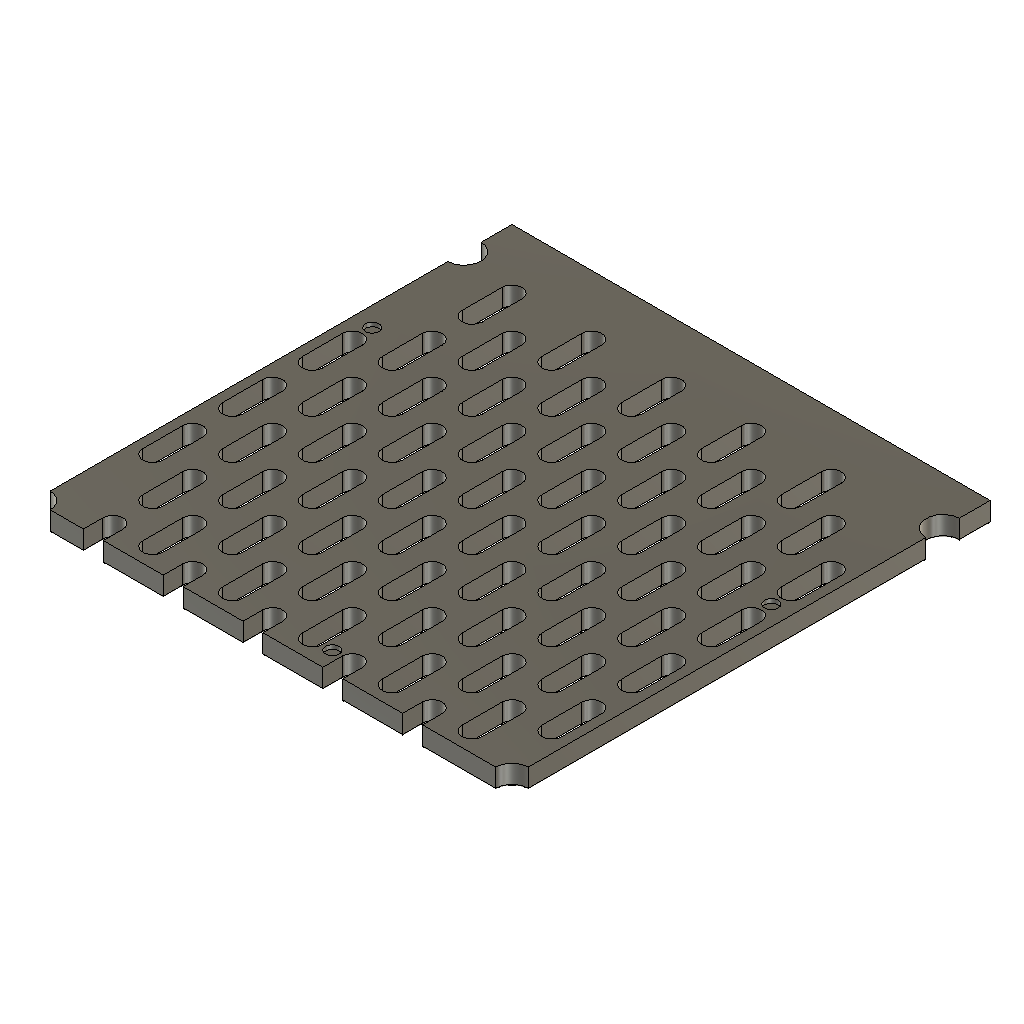
panel-top-edge-v02 (Autodesk Fusion 360 design; units mm, degrees)
part number: 2026-10-27-14-47-49-587
part number: 2026-10-27-14-47-50-048
Autodesk Fusion 360 part; units mm, degrees
sketch "01 Panel blank sketch" plane through (0, 0, 0) normal (0, 0, 1) x (1, 0, 0) in component "Panel top-edge"
  line L0 (0.1, 0.1) -> (119.9, 0.1)
  line L1 (119.9, 0.1) -> (119.9, 119.9)
  line L2 (119.9, 119.9) -> (0.1, 119.9)
  line L3 (0.1, 119.9) -> (0.1, 0.1)
  dimension "d31" = 0.1
  dimension "d32" = 0.1
  dimension "d33" = 119.8
  dimension "d34" = 119.8
  constraint horizontal L0
  constraint vertical L1
  constraint horizontal L2
  constraint vertical L3
  measures "d31" horizontal distance of origin L0.start
  measures "d32" vertical distance of origin L0.start
  measures "d33" horizontal distance of L0.start L0.end
  measures "d34" vertical distance of L0.end L1.end
extrude "01 Panel blank" add sketch "01 Panel blank sketch" along normal blind 5 in component "Panel top-edge"
sketch "03 A main constrained seed" plane through (0, 0, 0) normal (0, 0, 1) x (1, 0, 0) in component "Panel top-edge"
  line L0 (27.5, 5) -> (27.5, 15)
  arc A0 (27.5, 15) -> (22.5, 15) centre (25, 15) ccw
  line L1 (22.5, 15) -> (22.5, 5)
  arc A1 (22.5, 5) -> (27.5, 5) centre (25, 5) ccw
  line L2 (25, 5) -> (25, 15) construction
  line L3 (25, 5) -> (35, 5) construction
  dimension "d37" = 5
  dimension "d38" = 10
  dimension "d39" = 90
  dimension "d40" = 10
  dimension "d41" = 25
  dimension "d42" = 5
  constraint tangent L0 A0
  constraint tangent A0 L1
  constraint tangent L1 A1
  constraint tangent L0 A1
  constraint parallel L0 L1
  constraint horizontal L3
  measures "d37" diameter of A0
  measures "d38" distance of A1.centre A0.centre
  measures "d39" angle of L2 L3
  measures "d40" horizontal distance of A1.centre L3.end
  measures "d41" horizontal distance of origin A1.centre
  measures "d42" vertical distance of origin A1.centre
extrude "03 A main through cut" cut sketch "03 A main constrained seed" along normal blind 5 in component "Panel top-edge"
pattern_linear "03 A main lattice" count 5 spacing 20 along (1, 0, 0) count 5 spacing 20 along (0, 1, 0) of "03 A main through cut" in component "Panel top-edge"
sketch "04 A end strip constrained seed" plane through (0, 0, 0) normal (0, 0, 1) x (1, 0, 0) in component "Panel top-edge"
  line L0 (7.5, 25) -> (7.5, 35)
  arc A0 (7.5, 35) -> (2.5, 35) centre (5, 35) ccw
  line L1 (2.5, 35) -> (2.5, 25)
  arc A1 (2.5, 25) -> (7.5, 25) centre (5, 25) ccw
  line L2 (5, 25) -> (5, 35) construction
  line L3 (5, 25) -> (15, 25) construction
  dimension "d49" = 5
  dimension "d50" = 10
  dimension "d51" = 90
  dimension "d52" = 10
  dimension "d53" = 5
  dimension "d54" = 25
  constraint tangent L0 A0
  constraint tangent A0 L1
  constraint tangent L1 A1
  constraint tangent L0 A1
  constraint parallel L0 L1
  constraint horizontal L3
  measures "d49" diameter of A0
  measures "d50" distance of A1.centre A0.centre
  measures "d51" angle of L2 L3
  measures "d52" horizontal distance of A1.centre L3.end
  measures "d53" horizontal distance of origin A1.centre
  measures "d54" vertical distance of origin A1.centre
extrude "04 A end strip through cut" cut sketch "04 A end strip constrained seed" along normal blind 5 in component "Panel top-edge"
pattern_linear "04 A end strip lattice" count 1 spacing 20 along (1, 0, 0) count 3 spacing 20 along (0, 1, 0) of "04 A end strip through cut" in component "Panel top-edge"
sketch "05 B main constrained seed" plane through (0, 0, 0) normal (0, 0, 1) x (1, 0, 0) in component "Panel top-edge"
  line L0 (17.5, -5) -> (17.5, 5)
  arc A0 (17.5, 5) -> (12.5, 5) centre (15, 5) ccw
  line L1 (12.5, 5) -> (12.5, -5)
  arc A1 (12.5, -5) -> (17.5, -5) centre (15, -5) ccw
  line L2 (15, -5) -> (15, 5) construction
  line L3 (15, -5) -> (25, -5) construction
  dimension "d61" = 5
  dimension "d62" = 10
  dimension "d63" = 90
  dimension "d64" = 10
  dimension "d65" = 15
  dimension "d66" = 5
  constraint tangent L0 A0
  constraint tangent A0 L1
  constraint tangent L1 A1
  constraint tangent L0 A1
  constraint parallel L0 L1
  constraint horizontal L3
  measures "d61" diameter of A0
  measures "d62" distance of A1.centre A0.centre
  measures "d63" angle of L2 L3
  measures "d64" horizontal distance of A1.centre L3.end
  measures "d65" horizontal distance of origin A1.centre
  measures "d66" vertical distance of origin A1.centre
extrude "05 B main through cut" cut sketch "05 B main constrained seed" along normal blind 5 in component "Panel top-edge"
pattern_linear "05 B main lattice" count 5 spacing 20 along (1, 0, 0) count 6 spacing 20 along (0, 1, 0) of "05 B main through cut" in component "Panel top-edge"
sketch "06 B end strip constrained seed" plane through (0, 0, 0) normal (0, 0, 1) x (1, 0, 0) in component "Panel top-edge"
  line L0 (117.5, 15) -> (117.5, 25)
  arc A0 (117.5, 25) -> (112.5, 25) centre (115, 25) ccw
  line L1 (112.5, 25) -> (112.5, 15)
  arc A1 (112.5, 15) -> (117.5, 15) centre (115, 15) ccw
  line L2 (115, 15) -> (115, 25) construction
  line L3 (115, 15) -> (125, 15) construction
  dimension "d73" = 5
  dimension "d74" = 10
  dimension "d75" = 90
  dimension "d76" = 10
  dimension "d77" = 115
  dimension "d78" = 15
  constraint tangent L0 A0
  constraint tangent A0 L1
  constraint tangent L1 A1
  constraint tangent L0 A1
  constraint parallel L0 L1
  constraint horizontal L3
  measures "d73" diameter of A0
  measures "d74" distance of A1.centre A0.centre
  measures "d75" angle of L2 L3
  measures "d76" horizontal distance of A1.centre L3.end
  measures "d77" horizontal distance of origin A1.centre
  measures "d78" vertical distance of origin A1.centre
extrude "06 B end strip through cut" cut sketch "06 B end strip constrained seed" along normal blind 5 in component "Panel top-edge"
pattern_linear "06 B end strip lattice" count 1 spacing 20 along (1, 0, 0) count 4 spacing 20 along (0, 1, 0) of "06 B end strip through cut" in component "Panel top-edge"
sketch "07 Shared node clearance sketch" plane through (0, 0, 0) normal (0, 0, 1) x (1, 0, 0) in component "Panel top-edge"
  circle A0 centre (0, 0) radius 4.2
  dimension "d85" = 8.4
  constraint coincident A0.centre origin
  measures "d85" diameter of A0
extrude "07 Shared node clearance" cut sketch "07 Shared node clearance sketch" along normal blind 5 in component "Panel top-edge"
sketch "07 Shared node clearance sketch (1)" plane through (0, 0, 0) normal (0, 0, 1) x (1, 0, 0) in component "Panel top-edge"
  circle A0 centre (0, 108) radius 4.2
  dimension "d88" = 108
  dimension "d89" = 8.4
  constraint vertical origin A0.centre
  measures "d88" vertical distance of origin A0.centre
  measures "d89" diameter of A0
extrude "07 Shared node clearance (1)" cut sketch "07 Shared node clearance sketch (1)" along normal blind 5 in component "Panel top-edge"
sketch "07 Shared node clearance sketch (2)" plane through (0, 0, 0) normal (0, 0, 1) x (1, 0, 0) in component "Panel top-edge"
  circle A0 centre (120, 0) radius 4.2
  dimension "d92" = 120
  dimension "d93" = 8.4
  constraint horizontal origin A0.centre
  measures "d92" horizontal distance of origin A0.centre
  measures "d93" diameter of A0
extrude "07 Shared node clearance (2)" cut sketch "07 Shared node clearance sketch (2)" along normal blind 5 in component "Panel top-edge"
sketch "07 Shared node clearance sketch (3)" plane through (0, 0, 0) normal (0, 0, 1) x (1, 0, 0) in component "Panel top-edge"
  circle A0 centre (120, 108) radius 4.2
  dimension "d96" = 120
  dimension "d97" = 108
  dimension "d98" = 8.4
  measures "d96" horizontal distance of origin A0.centre
  measures "d97" vertical distance of origin A0.centre
  measures "d98" diameter of A0
extrude "07 Shared node clearance (3)" cut sketch "07 Shared node clearance sketch (3)" along normal blind 5 in component "Panel top-edge"
fillet "08 Rounded slot entrances and face edges" radius 0.4 2 faces at (51.7289, 115.7643, 0) (51.7289, 115.7643, 0) in component "Panel top-edge"
ref_plane "WorkPlane1" through (0, 0, 5) normal (0, 0, 1) x (1, 0, 0) in component "Panel top-edge"
sketch "09 Blind rear key socket sketch" plane through (0, 0, 5) normal (0, 0, 1) x (1, 0, 0) in component "Panel top-edge"
  circle A0 centre (5, 80) radius 1.7
  dimension "d105" = 5
  dimension "d106" = 80
  dimension "d107" = 3.4
  measures "d105" horizontal distance of origin A0.centre
  measures "d106" vertical distance of origin A0.centre
  measures "d107" diameter of A0
extrude "09 Blind rear key socket" cut sketch "09 Blind rear key socket sketch" against normal blind 1 in component "Panel top-edge"
ref_plane "WorkPlane2" through (0, 0, 5) normal (0, 0, 1) x (1, 0, 0) in component "Panel top-edge"
sketch "09 Blind rear key socket sketch (1)" plane through (0, 0, 5) normal (0, 0, 1) x (1, 0, 0) in component "Panel top-edge"
  circle A0 centre (115, 70) radius 1.7
  dimension "d112" = 115
  dimension "d113" = 70
  dimension "d114" = 3.4
  measures "d112" horizontal distance of origin A0.centre
  measures "d113" vertical distance of origin A0.centre
  measures "d114" diameter of A0
extrude "09 Blind rear key socket (1)" cut sketch "09 Blind rear key socket sketch (1)" against normal blind 1 in component "Panel top-edge"
ref_plane "WorkPlane3" through (0, 0, 5) normal (0, 0, 1) x (1, 0, 0) in component "Panel top-edge"
sketch "09 Blind rear key socket sketch (2)" plane through (0, 0, 5) normal (0, 0, 1) x (1, 0, 0) in component "Panel top-edge"
  circle A0 centre (70, 5) radius 1.7
  dimension "d119" = 70
  dimension "d120" = 5
  dimension "d121" = 3.4
  measures "d119" horizontal distance of origin A0.centre
  measures "d120" vertical distance of origin A0.centre
  measures "d121" diameter of A0
extrude "09 Blind rear key socket (2)" cut sketch "09 Blind rear key socket sketch (2)" against normal blind 1 in component "Panel top-edge"
component "Panel top-edge" placed x (1, 0, 0) y (0, 1, 0) z (0, 0, 1) at (0, 0, 0)
equation "columns = 6" comment "Even integer 4..14; each cell is 20 mm"
equation "rows = 6" comment "Even integer 4..14"
equation "pitch = 20 mm" comment "Keep for dense SKADIS compatible lattice"
equation "panelWidth = columns * pitch" comment "Nominal module pitch X"
equation "panelHeight = rows * pitch" comment "Nominal module pitch Y"
equation "seamGap = 0.2 mm" comment "Physical envelope shrinks around fixed lattice"
equation "boardThickness = 5 mm" comment "Fit-test with real hooks"
equation "slotWidth = 5 mm" comment "Minimum throat width"
equation "slotHeight = 15 mm" comment "Minimum throat height"
equation "entryRadius = 0.4 mm" comment "Front slot and perimeter edge rounding"
equation "cornerRadius = 6 mm" comment "Plan-view panel corner rounding"
equation "hookClearance = 10 mm" comment "PROVISIONAL: board rear to front of extrusion"
equation "frameZ = boardThickness + hookClearance" comment "Front extrusion datum"
equation "mountInset = 12 mm" comment "Exterior node inset from outside module edge"
equation "mountBore = 8.4 mm" comment "Clearance around 8 mm metal shoulder"
equation "capDiameter = 18 mm" comment "Visible decorative mounting disk"
equation "capThickness = 2 mm" comment "Metal clamping cap / washer"
equation "seatThickness = 2 mm" comment "Printed rear bearing washer"
equation "screwDiameter = 5 mm" comment "Nominal M5 reference, threads omitted"
equation "screwClearance = 5.5 mm" comment "Cap and spacer bore"
equation "keyWidth = 4 mm" comment "Registration key corridor width"
equation "keyThickness = 2 mm" comment "Rear removable key body"
equation "keyPegDiameter = 3 mm" comment "Rear locating peg"
equation "keySocketDiameter = 3.4 mm" comment "0.2 mm radial starting fit"
equation "keyPegHeight = 0.8 mm" comment "Peg penetration"
equation "keySocketDepth = 1 mm" comment "Blind locating pocket"
equation "panelLeft = 0" comment "0 internal / 1 finished; full cell border and inset mounting"
equation "panelRight = 0" comment "0 internal / 1 finished; full cell border and inset mounting"
equation "panelBottom = 0" comment "0 internal / 1 finished; full cell border and inset mounting"
equation "panelTop = 1" comment "0 internal / 1 finished; full cell border and inset mounting"
equation "d31 = abs(( 0 mm ) + seamGap / 2)"
equation "d32 = abs(( 0 mm ) + seamGap / 2)"
equation "d33 = panelWidth - seamGap"
equation "d34 = panelHeight - seamGap"
equation "d35 = boardThickness"
equation "d37 = slotWidth"
equation "d38 = slotHeight - slotWidth"
equation "d40 = pitch / 2"
equation "d41 = abs(( 0 mm ) + pitch / 4 + pitch * ( panelLeft + 1 ))"
equation "d42 = abs(( ( 0 mm ) + pitch / 2 + pitch * panelBottom ) - ( slotHeight - slotWidth ) / 2)"
equation "d43 = boardThickness"
equation "d45 = columns - panelLeft - panelRight - 1"
equation "d46 = rows - panelBottom - panelTop"
equation "d47 = pitch"
equation "d48 = pitch"
equation "d49 = slotWidth"
equation "d50 = slotHeight - slotWidth"
equation "d52 = pitch / 2"
equation "d53 = abs(( 0 mm ) + pitch / 4 + pitch * panelLeft)"
equation "d54 = abs(( ( 0 mm ) + 3 * pitch / 2 + pitch * panelBottom ) - ( slotHeight - slotWidth ) / 2)"
equation "d55 = boardThickness"
equation "d58 = rows - panelBottom - panelTop - 2"
equation "d59 = pitch"
equation "d60 = pitch"
equation "d61 = slotWidth"
equation "d62 = slotHeight - slotWidth"
equation "d64 = pitch / 2"
equation "d65 = abs(( 0 mm ) + 3 * pitch / 4 + pitch * panelLeft)"
equation "d66 = abs(( ( 0 mm ) + pitch * panelBottom ) - ( slotHeight - slotWidth ) / 2)"
equation "d67 = boardThickness"
equation "d69 = columns - panelLeft - panelRight - 1"
equation "d70 = rows + 1 - panelBottom - panelTop"
equation "d71 = pitch"
equation "d72 = pitch"
equation "d73 = slotWidth"
equation "d74 = slotHeight - slotWidth"
equation "d76 = pitch / 2"
equation "d77 = abs(( 0 mm ) + panelWidth - pitch / 4 - pitch * panelRight)"
equation "d78 = abs(( ( 0 mm ) + pitch + pitch * panelBottom ) - ( slotHeight - slotWidth ) / 2)"
equation "d79 = boardThickness"
equation "d82 = rows - 1 - panelBottom - panelTop"
equation "d83 = pitch"
equation "d84 = pitch"
equation "d85 = mountBore"
equation "d86 = boardThickness"
equation "d88 = abs(( 0 mm ) + panelHeight - mountInset * panelTop)"
equation "d89 = mountBore"
equation "d90 = boardThickness"
equation "d92 = abs(( 0 mm ) + panelWidth - mountInset * panelRight)"
equation "d93 = mountBore"
equation "d94 = boardThickness"
equation "d96 = abs(( 0 mm ) + panelWidth - mountInset * panelRight)"
equation "d97 = abs(( 0 mm ) + panelHeight - mountInset * panelTop)"
equation "d98 = mountBore"
equation "d99 = boardThickness"
equation "d102 = entryRadius"
equation "d103 = boardThickness"
equation "d105 = abs(( 0 mm ) + pitch / 4)"
equation "d106 = abs(( 0 mm ) + panelHeight / 2 + pitch)"
equation "d107 = keySocketDiameter"
equation "d108 = -keySocketDepth"
equation "d110 = boardThickness"
equation "d112 = abs(( 0 mm ) + panelWidth - pitch / 4)"
equation "d113 = abs(( 0 mm ) + panelHeight / 2 + pitch / 2)"
equation "d114 = keySocketDiameter"
equation "d115 = -keySocketDepth"
equation "d117 = boardThickness"
equation "d119 = abs(( 0 mm ) + panelWidth / 2 + pitch / 2)"
equation "d120 = abs(( 0 mm ) + pitch / 4)"
equation "d121 = keySocketDiameter"
equation "d122 = -keySocketDepth"
named bodies: "Panel top-edge"
